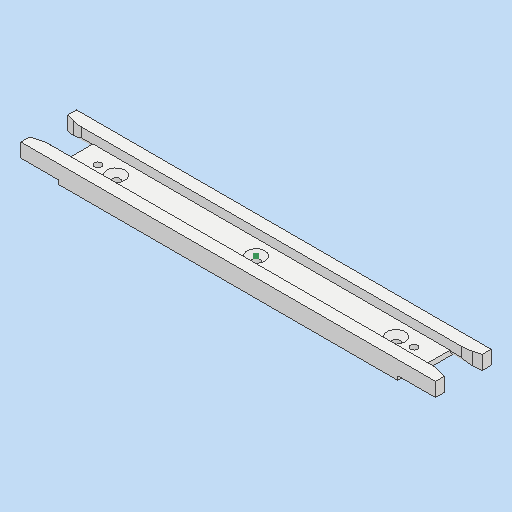
# Autodesk Inventor part: MM0948AN130_G01_116
Saved by Autodesk Inventor 2023.3 (Build 273359000, 359)
## iProperties
Part Number: MM0948AN130_G01_116
Material: Kst - POM (Delrin, weiss)
Description: =<RBPARTNOTITLE2>
Document SubType Name: Modeling
Designer: ric7an
Mass: 65.8207 g
Surface Area: 205.868 cm^2
Volume: 46.3526 cm^3
Density: 1.42 g/cm^3
Appearance: weiss AnP
Created: 2023-03-23
RBDOCUMENTTYPE: DRF
RBDOCUMENTVERSION: 00
RBDRAWINGMAINSCALE: 1:1
RBDRAWINGMISSINGSPEC: --
RBDRAWINGVOLUME: --
RBGBEDGESIN1: +0,5
RBGBEDGESIN2: +0,2
RBGBEDGESOUT1: -0,3
RBGBEDGESOUT2: -0,1
RBMATERIAL: =<Material>
RBMATMEETS: --
RBMATNO: =<Part Number>
RBPARTMADEOF: 10 x 31 x 276 (FM)
RBPARTNO: SIEHE MNR
RBPARTNOTITLE1: manufactured part
RBPARTNOTITLE2: Anfertigungsteil
RBPARTSAFETYINDICATOR: --
RBSURFACE: --
RBSURFACE2: --
RBZEDGESNORM: ISO13715:2002-06
RBZGENDIMCLASS: m
RBZGENDIMNORM: ISO 2768-1:1989-11
RBZGENGEOCLASS: H
RBZGENGEONORM: ISO 2768-2:1989-11
RBZSURFACENORM: ISO13D2:2002-02
RBZTOLERANCENORM: ISO 14405-1:2010-12
AnP_Material: =<Material>
AnP_TemplVers: 20190222
AnP_Kategorie: 1
MaxAbmaße: 10 x 31 x 276 (FM)
AnP_Kommentar_aktuell: =<Comments>
AnP_Material_aktuell: =<Material>
Author: FH/Wi
Keywords: =<RBPARTMADEOF>
Comments: =<RBSURFACE2>
Revision Number: 01
Autodesk Inventor part; units mm, degrees
ref_plane "YZ Plane" through (0, 0, 0) normal (1, 0, 0) x (0, 1, 0)
ref_plane "XZ Plane" through (0, 0, 0) normal (0, 1, 0) x (-1, 0, 0)
ref_plane "XY Plane" through (0, 0, 0) normal (0, 0, 1) x (1, 0, 0)
sketch "Skizze1" plane through (0, 0, 0) normal (0, 0, 1) x (1, 0, 0)
  line L0 (-115.5, 15.5) -> (115.5, 15.5)
  line L1 (115.5, 15.5) -> (115.5, -15.5)
  line L2 (115.5, -15.5) -> (-115.5, -15.5)
  line L3 (-115.5, -15.5) -> (-115.5, 15.5)
  line L4 (0, 21.7) -> (0, -21.7) projected
  line L5 (-161.7, 0) -> (161.7, 0) projected
  point P0 (0, 0)
  dimension "d0" = 31
  dimension "d1" = 231
  constraints: 8 end point, 2 parallel, 1 horizontal, 1 perpendicular, 2 other
  measures "d0" distance of L0.end L1.end
  measures "d1" distance of L0.start L0.end
extrude "Extrusion1" add sketch "Skizze1" along normal blind 10
sketch "Skizze2" plane through (0, 0, 10) normal (0, 0, 1) x (1, 0, 0)
  line L0 (115.5, 15.5) -> (-115.5, 15.5) projected
  line L1 (-115.5, 15.5) -> (-115.5, -15.5) projected
  line L2 (-115.5, -15.5) -> (115.5, -15.5) projected
  line L3 (115.5, -15.5) -> (115.5, 15.5) projected
  line L4 (-115.5, 10.5256) -> (-108.5, 8.65)
  line L5 (-108.5, 8.65) -> (108.5, 8.65)
  line L6 (108.5, 8.65) -> (115.5, 10.5256)
  line L7 (115.5, -10.5256) -> (108.5, -8.65)
  line L8 (108.5, -8.65) -> (-108.5, -8.65)
  line L9 (-108.5, -8.65) -> (-115.5, -10.5256)
  line L10 (0, 21.7) -> (0, -21.7) projected
  line L11 (-193.2, 0) -> (193.2, 0) projected
  point P0 (0, 0)
  dimension "d4" = 15
  dimension "d5" = 15
  dimension "d7" = 17.3
  dimension "d28" = 7
  constraints: 12 end point, 4 point on line, 2 vertical alignment, 1 horizontal, 1 parallel, 1 symmetric about line, 3 other
  measures "d4" angle of L8 L9
  measures "d5" angle of L8 L7
  measures "d7" distance between parallel lines of L8 L5
  measures "d28" distance from line of L4.end L1
extrude "Extrusion2" cut sketch "Skizze2" against normal blind 5 contours L3 L11 L10 L5 L6 | L10 L11 L1 L4 L5 | L3 L7 L8 L10 L11 | L10 L8 L9 L1 L11
fillet "Rundung1" radius 20 4 edges at (-108.5, -8.65, 7.5) (108.5, -8.65, 7.5) (108.5, 8.65, 7.5) (-108.5, 8.65, 7.5)
sketch "Skizze3" plane through (0, 0, 5) normal (0, 0, 1) x (1, 0, 0)
  line L0 (-161.7, 0) -> (161.7, 0) projected
  line L1 (0, 21.7) -> (0, -21.7) projected
  point P0 (0, 0)
  point P1 (-78, 0)
  point P2 (0, 0)
  point P3 (78, 0)
  dimension "d11" = 156
  constraints: 2 point on line, 1 coincident, 1 symmetric about line
  measures "d11" distance of point (78, 0) point (-78, 0)
hole "Bohrung1" at (-78, 0, 5) at (0, 0, 5) at (78, 0, 5) direction (0, 0, -1) diameter 4.5 end through all countersink diameter 10 countersink angle 90 clearance for "Innensechskant-Senkkopfschraube ISO 10642" size "M4" standard "ISO"
sketch "Skizze4" plane through (0, 0, 5) normal (0, 0, 1) x (1, 0, 0)
  line L0 (0, 21.7) -> (0, -21.7) projected
  line L1 (-161.7, 0) -> (161.7, 0) projected
  circle A0 centre (-78, 0) radius 5 projected
  point P0 (0, 0)
  point P1 (-88, 0)
  point P2 (88, 0)
  dimension "d27" = 10
  constraints: 1 point on line, 1 symmetric about line
  measures "d27" distance of A0.centre point (-88, 0)
hole "Bohrung2" at (-88, 0, 5) at (88, 0, 5) direction (0, 0, -1) diameter 4 end through all
sketch "Skizze5" plane through (0, 0, 0) normal (0, 0, -1) x (-1, 0, 0)
  line L0 (-115.5, 15.5) -> (-94.5, 15.5)
  line L1 (-94.5, 15.5) -> (-94.5, -15.5)
  line L2 (-94.5, -15.5) -> (-115.5, -15.5)
  line L3 (-115.5, -15.5) -> (-115.5, 15.5)
  line L4 (115.5, 15.5) -> (94.5, 15.5)
  line L5 (94.5, 15.5) -> (94.5, -15.5)
  line L6 (94.5, -15.5) -> (115.5, -15.5)
  line L7 (115.5, -15.5) -> (115.5, 15.5)
  line L8 (-115.5, -15.5) -> (115.5, -15.5) projected
  point P0 (0, 0)
  dimension "d29" = 21
  constraints: 16 end point, 4 parallel, 2 coincident, 2 horizontal, 2 perpendicular, 2 point on line, 1 collinear
  measures "d29" distance of L0.start L0.end
extrude "Extrusion3" cut sketch "Skizze5" against normal blind 2.2
sketch "Skizze6" plane through (0, 0, 5) normal (0, 0, 1) x (1, 0, 0)
  point P0 (0, 0)
sketch "Skizze7" plane through (-115.5, -10.5256, 5) normal (-1, 0, 0) x (0, 0, 1)
  line L0 (-2.8, 19.1756) -> (0, 19.1756)
  line L1 (0, 19.1756) -> (0, 1.8756)
  line L2 (0, 1.8756) -> (-2.8, 1.8756)
  line L3 (-2.8, 1.8756) -> (-2.8, 19.1756)
  line L4 (-2.8, 26.0256) -> (-2.8, -4.9744) projected
  line L5 (0, 0) -> (0, 21.0513) projected
  point P0 (-5, 10.5256)
  point P1 (-2.8, 10.5256)
  point P2 (5, 19.1756)
  constraints: 8 end point, 3 point on line, 2 parallel, 1 horizontal, 1 horizontal alignment, 1 midpoint, 1 perpendicular
extrude "Extrusion4" cut sketch "Skizze7" against normal blind 16
chamfer "Fase1" [suppressed]
fillet "Rundung2" radius 2.5 2 edges at (-107.5, 8.65, 2.2) (-107.5, -8.65, 2.2)
mirror "Spiegeln1" about plane through (0, 0, 0) normal (1, 0, 0) of "Extrusion3", "Extrusion4", "Rundung2"
sketch "Skizze8" plane through (0, 0, 5) normal (0, 0, 1) x (1, 0, 0)
  line L0 (-115.5, 8.65) -> (-105.867, 8.65) projected
  arc A0 (-111.0433, 9.3315) -> (-105.867, 8.65) centre (-105.867, 28.65) ccw projected
  line L1 (-115.5, 10.5256) -> (-111.0433, 9.3315) projected
  line L2 (-115.5, 8.65) -> (-115.5, 10.5256) projected
  line L3 (-105.867, -8.65) -> (-115.5, -8.65) projected
  line L4 (-115.5, -10.5256) -> (-115.5, -8.65) projected
  line L5 (-111.0433, -9.3315) -> (-115.5, -10.5256) projected
  arc A1 (-105.867, -8.65) -> (-111.0433, -9.3315) centre (-105.867, -28.65) ccw projected
  line L6 (115.5, -8.65) -> (105.867, -8.65) projected
  arc A2 (111.0433, -9.3315) -> (105.867, -8.65) centre (105.867, -28.65) ccw projected
  line L7 (115.5, -10.5256) -> (111.0433, -9.3315) projected
  line L8 (115.5, -8.65) -> (115.5, -10.5256) projected
  line L9 (105.867, 8.65) -> (115.5, 8.65) projected
  line L10 (115.5, 10.5256) -> (115.5, 8.65) projected
  line L11 (111.0433, 9.3315) -> (115.5, 10.5256) projected
  arc A3 (105.867, 8.65) -> (111.0433, 9.3315) centre (105.867, 28.65) ccw projected
  point P0 (0, 0)
extrude "Extrusion5" cut sketch "Skizze8" against normal through all
